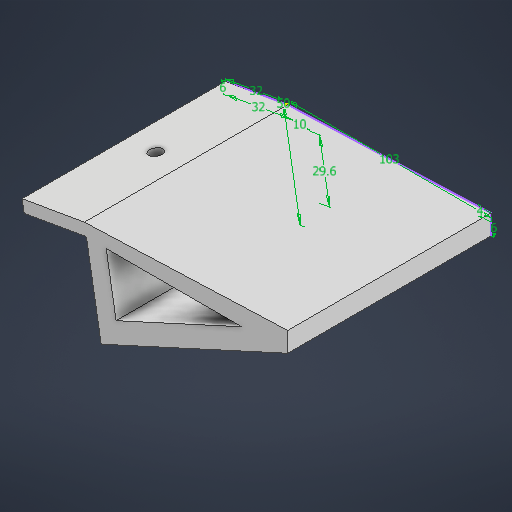
# Autodesk Inventor part: topmount
Saved by Autodesk Inventor 2026 (Build 300175000, 175)
## iProperties
Created: 2026-09-14
Part Number: topmount
Material: Generic
Document SubType Name: Modeling
Designer: Nitro
Density: 1 g/cm^3
Appearance: Default
Author: Nitro
Autodesk Inventor part; units mm, degrees
ref_plane "YZ Plane" through (0, 0, 0) normal (1, 0, 0) x (0, 1, 0)
ref_plane "XZ Plane" through (0, 0, 0) normal (0, 1, 0) x (-1, 0, 0)
ref_plane "XY Plane" through (0, 0, 0) normal (0, 0, 1) x (1, 0, 0)
sketch "Sketch1" plane through (0, 0, 0) normal (0, 0, 1) x (1, 0, 0)
  line L0 (0, 0) -> (103, 0)
  line L1 (103, 0) -> (103, 6)
  line L2 (103, 6) -> (0, 6)
  line L3 (0, 6) -> (-31.5319, 0.5468)
  line L4 (-31.5319, 0.5468) -> (-30.5095, -5.3654)
  line L5 (-30.5095, -5.3654) -> (0, 0)
  line L6 (103, 6) -> (103, 10)
  line L7 (103, 10) -> (0, 6)
  line L8 (-30.5095, -5.3654) -> (1.0069, 0.1771)
  line L9 (1.0069, 0.1771) -> (0, 6)
  line L10 (0, 6) -> (8.5195, -43.2688)
  line L11 (8.5195, -43.2688) -> (103, 0)
  line L12 (103, 0) -> (93, 0)
  line L13 (1.0375, 0) -> (11.0375, 0)
  line L14 (11.0375, 0) -> (16.0817, -29.167)
  line L15 (16.0817, -29.167) -> (79.7699, 0)
  line L16 (79.7699, 0) -> (103, 0)
  dimension "d0" = 103
  dimension "d1" = 6
  dimension "d3" = 32
  dimension "d4" = 6
  dimension "d45" = 4
  dimension "d48" = 32
  dimension "d49" = 50
  dimension "d51" = 10
  dimension "d52" = 29.6
  constraints: 34 end point, 5 point on line, 2 perpendicular, 1 collinear, 1 horizontal, 1 parallel, 1 vertical
  measures "d0" distance of L2.end L1.end
  measures "d1" distance of L0.end L1.end
  measures "d3" distance of L2.end L3.end
  measures "d4" distance of L3.end L4.end
  measures "d45" distance of L1.end L6.end
  measures "d48" distance of L4.end L8.end
  measures "d49" distance of L2.end L10.end
  measures "d51" distance of L13.start L13.end
  measures "d52" distance of L13.end L14.end
extrude "Extrusion5" add sketch "Sketch1" along normal blind 103 contours L8 L10 L0 | L5 L4 L3 L9 L8 | L10 L9 L2 L1 L0
sketch "Sketch9" plane through (0, 6, 0) normal (0, 1, 0) x (1, 0, 0)
  line L0 (103, 0) -> (0, 0) projected
  circle A0 centre (51.5, -51.5) radius 3.25
  line L1 (0, 0) -> (-31.5319, 0) projected
  circle A1 centre (-15.5, -51.5) radius 3.25
  dimension "d34" = 6.5
  dimension "d37" = 6.5
  constraints: 2 centre point
  measures "d34" diameter of A0
  measures "d37" diameter of A1
extrude "Extrusion6" cut sketch "Sketch9" along normal mid plane 40 contours A0
sketch "Sketch10" plane through (-31.5319, 0.5468, 103) normal (-0.1704, 0.9854, 0) x (0.9854, 0.1704, 0)
  line L0 (32, 103) -> (32, 0) projected
  line L1 (32, 0) -> (0, 0) projected
  circle A0 centre (16.5, 51.5) radius 3.25
  point P0 (30.9775, 103)
  dimension "d42" = 6.5
  constraints: 1 centre point
  measures "d42" diameter of A0
extrude "Extrusion7" cut sketch "Sketch10" against normal blind 6
extrude "Extrusion8" add sketch "Sketch1" along normal blind 103 contours L7 L6 L2
sketch "Sketch12" plane through (0, 6, 103) normal (-0.0388, 0.9992, 0) x (0.9992, 0.0388, 0)
  point P0 (-0.2328, 103)
extrude "Extrusion9" add sketch "Sketch1" along normal blind 103 contours L0 L14 L15 L11 L10
body "Solid2"
